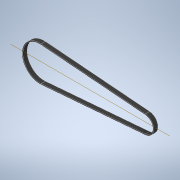
# Autodesk Inventor part: TiminigBelt_G
Saved by Autodesk Inventor 2021 (Build 250183000, 183)
## iProperties
Created: 2025-11-24
Part Number: TiminigBelt_G
Material: Rubber, Silicone
Document SubType Name: Modeling
Designer: Admin
Density: 1.25 g/cm^3
Appearance: Rubber - Black
Author: Admin
Autodesk Inventor part; units mm, degrees
ref_plane "YZ Plane" through (0, 0, 0) normal (1, 0, 0) x (0, 1, 0)
ref_plane "XZ Plane" through (0, 0, 0) normal (0, 1, 0) x (-1, 0, 0)
ref_plane "XY Plane" through (0, 0, 0) normal (0, 0, 1) x (1, 0, 0)
sketch "Sketch1" plane through (0, 0, 0) normal (0, 0, 1) x (1, 0, 0)
  arc A0 (5.1085, 62.5417) -> (5.1085, -62.5417) centre (0, 0) ccw
  arc A1 (392.5237, -30.8971) -> (392.5237, 30.8971) centre (390, 0) ccw
  line L0 (5.1085, 62.5417) -> (392.5237, 30.8971)
  line L1 (5.1085, -62.5417) -> (392.5237, -30.8971)
  line L2 (-163.7, 0) -> (521.95, 0) projected
  line L3 (392.7679, 33.8871) -> (5.3527, 65.5318)
  arc A2 (5.3527, 65.5318) -> (5.3527, -65.5318) centre (0, 0) ccw
  line L4 (5.3527, -65.5318) -> (392.7679, -33.8871)
  arc A3 (392.7679, -33.8871) -> (392.7679, 33.8871) centre (390, 0) ccw
  dimension "d0" = 390
  dimension "d1" = 125.5
  dimension "d2" = 62
  dimension "d3" = 0
  dimension "d20" = 3
  constraints: 8 end point, 8 point on circle, 4 centre point, 4 tangent, 1 coincident, 3 other
  measures "d0" distance of A1.centre point (0, 0)
  measures "d1" diameter of A0
  measures "d2" diameter of A1
  measures "d3" vertical distance of point (0, 0) A1.centre
  measures "d20" distance between parallel lines of L0 L3
extrude "Extrusion2" add sketch "Sketch1" along normal mid plane 16 contours A0 L2 A2 L3 A3 A1 L0 | A0 L1 A1 L2 A3 L4 A2
body "Solid2"
